210101_P01_WALL-PANEL-ASSY-SIDE-LOWER-LH_CAD (Autodesk Fusion 360 design; units mm, degrees)
part number: 2026-10-31-21-33-22-907
description: WALL - PANEL FRAME - SIDE LOWER - LH | Vách trái - khung dưới | P01
part number: 211101
description: WALL - SKIN - SIDE LOWER - LH | Vách trái - tấm ốp alu dưới | P01
part number: 211301
description: WALL - CAVITY FILL - SIDE LOWER - LH | Vách trái - bông PET dưới | P01
part number: 211501
description: HARDWARE - STOP WASHER - Ø10.5 X Ø20 X 1.5 - AL | Long đen chặn nhôm | P01
part number: 831002
description: HARDWARE - RIVET NUT - M6 - SHEREX CAH3-610-4.2 | Tán rút M6 | P01
part number: 838003
description: HARDWARE - LOCATING SPIGOT - M6 X Ø8 - STAINLESS | Chốt định vị Ø8 | P01
part number: 831001
Autodesk Fusion 360 part; units mm, degrees
(part 1 of 2)
ref_plane "WorkPlane1" through (0, 0, 112.26) normal (0, 0, 1) x (1, 0, 0) in component "211101 WALL - PANEL FRAME - SIDE LOWER - LH"
sketch "SKETCH - RAIL - BOTTOM TUBE" plane through (0, 0, 112.26) normal (0, 0, 1) x (1, 0, 0) in component "211101 WALL - PANEL FRAME - SIDE LOWER - LH"
  line L0 (-1244, -642.74) -> (-1204, -642.74)
  line L1 (-1204, -642.74) -> (-1204, 847)
  line L2 (-1204, 847) -> (-1244, 847)
  line L3 (-1244, 847) -> (-1244, -642.74)
  dimension "d1746" = 40
  dimension "d1747" = 1489.74
  dimension "d1748" = 1244
  dimension "d1749" = 642.74
  constraint horizontal L0
  constraint vertical L1
  constraint horizontal L2
  constraint vertical L3
  measures "d1746" horizontal distance of L0.start L0.end
  measures "d1747" vertical distance of L0.start L2.end
  measures "d1748" horizontal distance of origin L0.start
  measures "d1749" vertical distance of origin L0.start
extrude "EXTRUDE - RAIL - BOTTOM TUBE" add sketch "SKETCH - RAIL - BOTTOM TUBE" along normal blind 20 makes body 1 in component "211101 WALL - PANEL FRAME - SIDE LOWER - LH"
ref_plane "WorkPlane2" through (0, 0, 113.46) normal (0, 0, 1) x (1, 0, 0) in component "211101 WALL - PANEL FRAME - SIDE LOWER - LH"
sketch "SKETCH - RAIL - BOTTOM BORE" plane through (0, 0, 113.46) normal (0, 0, 1) x (1, 0, 0) in component "211101 WALL - PANEL FRAME - SIDE LOWER - LH"
  line L0 (-1242.8, -642.74) -> (-1205.2, -642.74)
  line L1 (-1205.2, -642.74) -> (-1205.2, 847)
  line L2 (-1205.2, 847) -> (-1242.8, 847)
  line L3 (-1242.8, 847) -> (-1242.8, -642.74)
  dimension "d1754" = 37.6
  dimension "d1755" = 1489.74
  dimension "d1756" = 1242.8
  dimension "d1757" = 642.74
  constraint horizontal L0
  constraint vertical L1
  constraint horizontal L2
  constraint vertical L3
  measures "d1754" horizontal distance of L0.start L0.end
  measures "d1755" vertical distance of L0.start L2.end
  measures "d1756" horizontal distance of origin L0.start
  measures "d1757" vertical distance of origin L0.start
extrude "CUT - RAIL - BOTTOM BORE" cut sketch "SKETCH - RAIL - BOTTOM BORE" along normal blind 17.6 bodies 1 in component "211101 WALL - PANEL FRAME - SIDE LOWER - LH"
ref_plane "WorkPlane3" through (0, 0, 1235) normal (0, 0, 1) x (1, 0, 0) in component "211101 WALL - PANEL FRAME - SIDE LOWER - LH"
sketch "SKETCH - RAIL - TOP TUBE" plane through (0, 0, 1235) normal (0, 0, 1) x (1, 0, 0) in component "211101 WALL - PANEL FRAME - SIDE LOWER - LH"
  line L0 (-1244, -642.74) -> (-1204, -642.74)
  line L1 (-1204, -642.74) -> (-1204, 847)
  line L2 (-1204, 847) -> (-1244, 847)
  line L3 (-1244, 847) -> (-1244, -642.74)
  dimension "d1762" = 40
  dimension "d1763" = 1489.74
  dimension "d1764" = 1244
  dimension "d1765" = 642.74
  constraint horizontal L0
  constraint vertical L1
  constraint horizontal L2
  constraint vertical L3
  measures "d1762" horizontal distance of L0.start L0.end
  measures "d1763" vertical distance of L0.start L2.end
  measures "d1764" horizontal distance of origin L0.start
  measures "d1765" vertical distance of origin L0.start
extrude "EXTRUDE - RAIL - TOP TUBE" add sketch "SKETCH - RAIL - TOP TUBE" along normal blind 20 separate body makes body 2 in component "211101 WALL - PANEL FRAME - SIDE LOWER - LH"
ref_plane "WorkPlane4" through (0, 0, 1236.2) normal (0, 0, 1) x (1, 0, 0) in component "211101 WALL - PANEL FRAME - SIDE LOWER - LH"
sketch "SKETCH - RAIL - TOP BORE" plane through (0, 0, 1236.2) normal (0, 0, 1) x (1, 0, 0) in component "211101 WALL - PANEL FRAME - SIDE LOWER - LH"
  line L0 (-1242.8, -642.74) -> (-1205.2, -642.74)
  line L1 (-1205.2, -642.74) -> (-1205.2, 847)
  line L2 (-1205.2, 847) -> (-1242.8, 847)
  line L3 (-1242.8, 847) -> (-1242.8, -642.74)
  dimension "d1770" = 37.6
  dimension "d1771" = 1489.74
  dimension "d1772" = 1242.8
  dimension "d1773" = 642.74
  constraint horizontal L0
  constraint vertical L1
  constraint horizontal L2
  constraint vertical L3
  measures "d1770" horizontal distance of L0.start L0.end
  measures "d1771" vertical distance of L0.start L2.end
  measures "d1772" horizontal distance of origin L0.start
  measures "d1773" vertical distance of origin L0.start
extrude "CUT - RAIL - TOP BORE" cut sketch "SKETCH - RAIL - TOP BORE" along normal blind 17.6 bodies 2 in component "211101 WALL - PANEL FRAME - SIDE LOWER - LH"
ref_plane "WorkPlane5" through (0, 0, 132.26) normal (0, 0, 1) x (1, 0, 0) in component "211101 WALL - PANEL FRAME - SIDE LOWER - LH"
sketch "SKETCH - STILE - FRONT TUBE" plane through (0, 0, 132.26) normal (0, 0, 1) x (1, 0, 0) in component "211101 WALL - PANEL FRAME - SIDE LOWER - LH"
  line L0 (-1244, -642.74) -> (-1204, -642.74)
  line L1 (-1204, -642.74) -> (-1204, -622.74)
  line L2 (-1204, -622.74) -> (-1244, -622.74)
  line L3 (-1244, -622.74) -> (-1244, -642.74)
  dimension "d1778" = 40
  dimension "d1779" = 20
  dimension "d1780" = 1244
  dimension "d1781" = 642.74
  constraint horizontal L0
  constraint vertical L1
  constraint horizontal L2
  constraint vertical L3
  measures "d1778" horizontal distance of L0.start L0.end
  measures "d1779" vertical distance of L0.start L2.end
  measures "d1780" horizontal distance of origin L0.start
  measures "d1781" vertical distance of origin L0.start
extrude "EXTRUDE - STILE - FRONT TUBE" add sketch "SKETCH - STILE - FRONT TUBE" along normal blind 1102.74 separate body makes body 3 in component "211101 WALL - PANEL FRAME - SIDE LOWER - LH"
ref_plane "WorkPlane6" through (0, 0, 132.26) normal (0, 0, 1) x (1, 0, 0) in component "211101 WALL - PANEL FRAME - SIDE LOWER - LH"
sketch "SKETCH - STILE - FRONT BORE" plane through (0, 0, 132.26) normal (0, 0, 1) x (1, 0, 0) in component "211101 WALL - PANEL FRAME - SIDE LOWER - LH"
  line L0 (-1242.8, -641.54) -> (-1205.2, -641.54)
  line L1 (-1205.2, -641.54) -> (-1205.2, -623.94)
  line L2 (-1205.2, -623.94) -> (-1242.8, -623.94)
  line L3 (-1242.8, -623.94) -> (-1242.8, -641.54)
  dimension "d1786" = 37.6
  dimension "d1787" = 17.6
  dimension "d1788" = 1242.8
  dimension "d1789" = 641.54
  constraint horizontal L0
  constraint vertical L1
  constraint horizontal L2
  constraint vertical L3
  measures "d1786" horizontal distance of L0.start L0.end
  measures "d1787" vertical distance of L0.start L2.end
  measures "d1788" horizontal distance of origin L0.start
  measures "d1789" vertical distance of origin L0.start
extrude "CUT - STILE - FRONT BORE" cut sketch "SKETCH - STILE - FRONT BORE" along normal blind 1102.74 bodies 3 in component "211101 WALL - PANEL FRAME - SIDE LOWER - LH"
ref_plane "WorkPlane7" through (0, 0, 132.26) normal (0, 0, 1) x (1, 0, 0) in component "211101 WALL - PANEL FRAME - SIDE LOWER - LH"
sketch "SKETCH - STILE - BACK TUBE" plane through (0, 0, 132.26) normal (0, 0, 1) x (1, 0, 0) in component "211101 WALL - PANEL FRAME - SIDE LOWER - LH"
  line L0 (-1244, 807) -> (-1204, 807)
  line L1 (-1204, 807) -> (-1204, 847)
  line L2 (-1204, 847) -> (-1244, 847)
  line L3 (-1244, 847) -> (-1244, 807)
  dimension "d1794" = 40
  dimension "d1795" = 40
  dimension "d1796" = 1244
  dimension "d1797" = 807
  constraint horizontal L0
  constraint vertical L1
  constraint horizontal L2
  constraint vertical L3
  measures "d1794" horizontal distance of L0.start L0.end
  measures "d1795" vertical distance of L0.start L2.end
  measures "d1796" horizontal distance of origin L0.start
  measures "d1797" vertical distance of origin L0.start
extrude "EXTRUDE - STILE - BACK TUBE" add sketch "SKETCH - STILE - BACK TUBE" along normal blind 1102.74 separate body makes body 4 in component "211101 WALL - PANEL FRAME - SIDE LOWER - LH"
ref_plane "WorkPlane8" through (0, 0, 132.26) normal (0, 0, 1) x (1, 0, 0) in component "211101 WALL - PANEL FRAME - SIDE LOWER - LH"
sketch "SKETCH - STILE - BACK BORE" plane through (0, 0, 132.26) normal (0, 0, 1) x (1, 0, 0) in component "211101 WALL - PANEL FRAME - SIDE LOWER - LH"
  line L0 (-1242.8, 808.2) -> (-1205.2, 808.2)
  line L1 (-1205.2, 808.2) -> (-1205.2, 845.8)
  line L2 (-1205.2, 845.8) -> (-1242.8, 845.8)
  line L3 (-1242.8, 845.8) -> (-1242.8, 808.2)
  dimension "d1802" = 37.6
  dimension "d1803" = 37.6
  dimension "d1804" = 1242.8
  dimension "d1805" = 808.2
  constraint horizontal L0
  constraint vertical L1
  constraint horizontal L2
  constraint vertical L3
  measures "d1802" horizontal distance of L0.start L0.end
  measures "d1803" vertical distance of L0.start L2.end
  measures "d1804" horizontal distance of origin L0.start
  measures "d1805" vertical distance of origin L0.start
extrude "CUT - STILE - BACK BORE" cut sketch "SKETCH - STILE - BACK BORE" along normal blind 1102.74 bodies 4 in component "211101 WALL - PANEL FRAME - SIDE LOWER - LH"
ref_plane "WorkPlane9" through (0, 0, 132.26) normal (0, 0, 1) x (1, 0, 0) in component "211101 WALL - PANEL FRAME - SIDE LOWER - LH"
sketch "SKETCH - STILE - MID 1 TUBE" plane through (0, 0, 132.26) normal (0, 0, 1) x (1, 0, 0) in component "211101 WALL - PANEL FRAME - SIDE LOWER - LH"
  line L0 (-1244, -277.805) -> (-1204, -277.805)
  line L1 (-1204, -277.805) -> (-1204, -257.805)
  line L2 (-1204, -257.805) -> (-1244, -257.805)
  line L3 (-1244, -257.805) -> (-1244, -277.805)
  dimension "d1810" = 40
  dimension "d1811" = 20
  dimension "d1812" = 1244
  dimension "d1813" = 277.805
  constraint horizontal L0
  constraint vertical L1
  constraint horizontal L2
  constraint vertical L3
  measures "d1810" horizontal distance of L0.start L0.end
  measures "d1811" vertical distance of L0.start L2.end
  measures "d1812" horizontal distance of origin L0.start
  measures "d1813" vertical distance of origin L0.start
extrude "EXTRUDE - STILE - MID 1 TUBE" add sketch "SKETCH - STILE - MID 1 TUBE" along normal blind 1102.74 separate body makes body 5 in component "211101 WALL - PANEL FRAME - SIDE LOWER - LH"
ref_plane "WorkPlane10" through (0, 0, 132.26) normal (0, 0, 1) x (1, 0, 0) in component "211101 WALL - PANEL FRAME - SIDE LOWER - LH"
sketch "SKETCH - STILE - MID 1 BORE" plane through (0, 0, 132.26) normal (0, 0, 1) x (1, 0, 0) in component "211101 WALL - PANEL FRAME - SIDE LOWER - LH"
  line L0 (-1243, -276.805) -> (-1205, -276.805)
  line L1 (-1205, -276.805) -> (-1205, -258.805)
  line L2 (-1205, -258.805) -> (-1243, -258.805)
  line L3 (-1243, -258.805) -> (-1243, -276.805)
  dimension "d1818" = 38
  dimension "d1819" = 18
  dimension "d1820" = 1243
  dimension "d1821" = 276.805
  constraint horizontal L0
  constraint vertical L1
  constraint horizontal L2
  constraint vertical L3
  measures "d1818" horizontal distance of L0.start L0.end
  measures "d1819" vertical distance of L0.start L2.end
  measures "d1820" horizontal distance of origin L0.start
  measures "d1821" vertical distance of origin L0.start
extrude "CUT - STILE - MID 1 BORE" cut sketch "SKETCH - STILE - MID 1 BORE" along normal blind 1102.74 bodies 5 in component "211101 WALL - PANEL FRAME - SIDE LOWER - LH"
pattern_linear "PATTERN - STILES - MID" count 3 spacing 364.935 along (0, 1, 0) of bodies 5 makes body 6 at (-1217.3333, 107.13, 499.84) makes body 7 at (-1217.3333, 472.065, 499.84) in component "211101 WALL - PANEL FRAME - SIDE LOWER - LH"
ref_plane "WorkPlane1" through (0, 0, 112.26) normal (0, 0, 1) x (1, 0, 0) in component "211301 WALL - SKIN - SIDE LOWER - LH"
sketch "SKETCH - SKIN PLATE" plane through (0, 0, 112.26) normal (0, 0, 1) x (1, 0, 0) in component "211301 WALL - SKIN - SIDE LOWER - LH"
  line L0 (-1250, -642.74) -> (-1247, -642.74)
  line L1 (-1247, -642.74) -> (-1247, 850)
  line L2 (-1247, 850) -> (-1250, 850)
  line L3 (-1250, 850) -> (-1250, -642.74)
  dimension "d1830" = 3
  dimension "d1831" = 1492.74
  dimension "d1832" = 1250
  dimension "d1833" = 642.74
  constraint horizontal L0
  constraint vertical L1
  constraint horizontal L2
  constraint vertical L3
  measures "d1830" horizontal distance of L0.start L0.end
  measures "d1831" vertical distance of L0.start L2.end
  measures "d1832" horizontal distance of origin L0.start
  measures "d1833" vertical distance of origin L0.start
extrude "EXTRUDE - SKIN PLATE" add sketch "SKETCH - SKIN PLATE" along normal blind 1142.74 separate body makes body 8 in component "211301 WALL - SKIN - SIDE LOWER - LH"
ref_plane "WorkPlane2" through (0, 0, 112.26) normal (0, 0, 1) x (1, 0, 0) in component "211301 WALL - SKIN - SIDE LOWER - LH"
sketch "SKETCH - SKIN BACK RETURN" plane through (0, 0, 112.26) normal (0, 0, 1) x (1, 0, 0) in component "211301 WALL - SKIN - SIDE LOWER - LH"
  line L0 (-1247, 847) -> (-1204, 847)
  line L1 (-1204, 847) -> (-1204, 850)
  line L2 (-1204, 850) -> (-1247, 850)
  line L3 (-1247, 850) -> (-1247, 847)
  dimension "d1838" = 43
  dimension "d1839" = 3
  dimension "d1840" = 1247
  dimension "d1841" = 847
  constraint horizontal L0
  constraint vertical L1
  constraint horizontal L2
  constraint vertical L3
  measures "d1838" horizontal distance of L0.start L0.end
  measures "d1839" vertical distance of L0.start L2.end
  measures "d1840" horizontal distance of origin L0.start
  measures "d1841" vertical distance of origin L0.start
extrude "JOIN - SKIN BACK RETURN" add sketch "SKETCH - SKIN BACK RETURN" along normal blind 1142.74 bodies 8 in component "211301 WALL - SKIN - SIDE LOWER - LH"
ref_plane "WorkPlane1" through (0, 0, 132.26) normal (0, 0, 1) x (1, 0, 0) in component "211501 WALL - CAVITY FILL - SIDE LOWER - LH"
sketch "SKETCH - FILL BAY 1" plane through (0, 0, 132.26) normal (0, 0, 1) x (1, 0, 0) in component "211501 WALL - CAVITY FILL - SIDE LOWER - LH"
  line L0 (-1244, -622.74) -> (-1204, -622.74)
  line L1 (-1204, -622.74) -> (-1204, -277.805)
  line L2 (-1204, -277.805) -> (-1244, -277.805)
  line L3 (-1244, -277.805) -> (-1244, -622.74)
  dimension "d1846" = 40
  dimension "d1847" = 344.935
  dimension "d1848" = 1244
  dimension "d1849" = 622.74
  constraint horizontal L0
  constraint vertical L1
  constraint horizontal L2
  constraint vertical L3
  measures "d1846" horizontal distance of L0.start L0.end
  measures "d1847" vertical distance of L0.start L2.end
  measures "d1848" horizontal distance of origin L0.start
  measures "d1849" vertical distance of origin L0.start
extrude "EXTRUDE - FILL BAY 1" add sketch "SKETCH - FILL BAY 1" along normal blind 1102.74 separate body makes body 9 in component "211501 WALL - CAVITY FILL - SIDE LOWER - LH"
pattern_linear "PATTERN - FILL BAYS" count 3 spacing 364.935 along (0, 1, 0) of bodies 9 makes body 10 at (-1244, -27.8483, 499.84) makes body 11 at (-1244, 337.0867, 499.84) in component "211501 WALL - CAVITY FILL - SIDE LOWER - LH"
ref_plane "WorkPlane2" through (0, 0, 132.26) normal (0, 0, 1) x (1, 0, 0) in component "211501 WALL - CAVITY FILL - SIDE LOWER - LH"
sketch "SKETCH - FILL BAY LAST" plane through (0, 0, 132.26) normal (0, 0, 1) x (1, 0, 0) in component "211501 WALL - CAVITY FILL - SIDE LOWER - LH"
  line L0 (-1244, 472.065) -> (-1204, 472.065)
  line L1 (-1204, 472.065) -> (-1204, 807)
  line L2 (-1204, 807) -> (-1244, 807)
  line L3 (-1244, 807) -> (-1244, 472.065)
  dimension "d1858" = 40
  dimension "d1859" = 334.935
  dimension "d1860" = 1244
  dimension "d1861" = 472.065
  constraint horizontal L0
  constraint vertical L1
  constraint horizontal L2
  constraint vertical L3
  measures "d1858" horizontal distance of L0.start L0.end
  measures "d1859" vertical distance of L0.start L2.end
  measures "d1860" horizontal distance of origin L0.start
  measures "d1861" vertical distance of origin L0.start
extrude "EXTRUDE - FILL BAY LAST" add sketch "SKETCH - FILL BAY LAST" along normal blind 1102.74 separate body makes body 12 in component "211501 WALL - CAVITY FILL - SIDE LOWER - LH"
ref_plane "WorkPlane3" through (0, 0, 132.26) normal (0, 0, 1) x (1, 0, 0) in component "211501 WALL - CAVITY FILL - SIDE LOWER - LH"
sketch "SKETCH - FILL POCKET BOTTOM BOLT 1" plane through (0, 0, 132.26) normal (0, 0, 1) x (1, 0, 0) in component "211501 WALL - CAVITY FILL - SIDE LOWER - LH"
  line L0 (-1244, -452.74) -> (-1204, -452.74)
  line L1 (-1204, -452.74) -> (-1204, -392.74)
  line L2 (-1204, -392.74) -> (-1244, -392.74)
  line L3 (-1244, -392.74) -> (-1244, -452.74)
  dimension "d1866" = 40
  dimension "d1867" = 60
  dimension "d1868" = 1244
  dimension "d1869" = 452.74
  constraint horizontal L0
  constraint vertical L1
  constraint horizontal L2
  constraint vertical L3
  measures "d1866" horizontal distance of L0.start L0.end
  measures "d1867" vertical distance of L0.start L2.end
  measures "d1868" horizontal distance of origin L0.start
  measures "d1869" vertical distance of origin L0.start
extrude "CUT - FILL POCKET BOTTOM BOLT 1" cut sketch "SKETCH - FILL POCKET BOTTOM BOLT 1" along normal blind 60 bodies 9 in component "211501 WALL - CAVITY FILL - SIDE LOWER - LH"
ref_plane "WorkPlane4" through (0, 0, 132.26) normal (0, 0, 1) x (1, 0, 0) in component "211501 WALL - CAVITY FILL - SIDE LOWER - LH"
sketch "SKETCH - FILL POCKET BOTTOM BOLT 2" plane through (0, 0, 132.26) normal (0, 0, 1) x (1, 0, 0) in component "211501 WALL - CAVITY FILL - SIDE LOWER - LH"
  line L0 (-1244, -101.8267) -> (-1204, -101.8267)
  line L1 (-1204, -101.8267) -> (-1204, -41.8267)
  line L2 (-1204, -41.8267) -> (-1244, -41.8267)
  line L3 (-1244, -41.8267) -> (-1244, -101.8267)
  dimension "d1874" = 40
  dimension "d1875" = 60
  dimension "d1876" = 1244
  dimension "d1877" = 101.8267
  constraint horizontal L0
  constraint vertical L1
  constraint horizontal L2
  constraint vertical L3
  measures "d1874" horizontal distance of L0.start L0.end
  measures "d1875" vertical distance of L0.start L2.end
  measures "d1876" horizontal distance of origin L0.start
  measures "d1877" vertical distance of origin L0.start
extrude "CUT - FILL POCKET BOTTOM BOLT 2" cut sketch "SKETCH - FILL POCKET BOTTOM BOLT 2" along normal blind 60 bodies 10 in component "211501 WALL - CAVITY FILL - SIDE LOWER - LH"
ref_plane "WorkPlane5" through (0, 0, 132.26) normal (0, 0, 1) x (1, 0, 0) in component "211501 WALL - CAVITY FILL - SIDE LOWER - LH"
sketch "SKETCH - FILL POCKET BOTTOM BOLT 3" plane through (0, 0, 132.26) normal (0, 0, 1) x (1, 0, 0) in component "211501 WALL - CAVITY FILL - SIDE LOWER - LH"
  line L0 (-1244, 249.0867) -> (-1204, 249.0867)
  line L1 (-1204, 249.0867) -> (-1204, 309.0867)
  line L2 (-1204, 309.0867) -> (-1244, 309.0867)
  line L3 (-1244, 309.0867) -> (-1244, 249.0867)
  dimension "d1882" = 40
  dimension "d1883" = 60
  dimension "d1884" = 1244
  dimension "d1885" = 249.0867
  constraint horizontal L0
  constraint vertical L1
  constraint horizontal L2
  constraint vertical L3
  measures "d1882" horizontal distance of L0.start L0.end
  measures "d1883" vertical distance of L0.start L2.end
  measures "d1884" horizontal distance of origin L0.start
  measures "d1885" vertical distance of origin L0.start
extrude "CUT - FILL POCKET BOTTOM BOLT 3" cut sketch "SKETCH - FILL POCKET BOTTOM BOLT 3" along normal blind 60 bodies 11 in component "211501 WALL - CAVITY FILL - SIDE LOWER - LH"
ref_plane "WorkPlane6" through (0, 0, 132.26) normal (0, 0, 1) x (1, 0, 0) in component "211501 WALL - CAVITY FILL - SIDE LOWER - LH"
sketch "SKETCH - FILL POCKET BOTTOM BOLT 4" plane through (0, 0, 132.26) normal (0, 0, 1) x (1, 0, 0) in component "211501 WALL - CAVITY FILL - SIDE LOWER - LH"
  line L0 (-1244, 600) -> (-1204, 600)
  line L1 (-1204, 600) -> (-1204, 660)
  line L2 (-1204, 660) -> (-1244, 660)
  line L3 (-1244, 660) -> (-1244, 600)
  dimension "d1890" = 40
  dimension "d1891" = 60
  dimension "d1892" = 1244
  dimension "d1893" = 600
  constraint horizontal L0
  constraint vertical L1
  constraint horizontal L2
  constraint vertical L3
  measures "d1890" horizontal distance of L0.start L0.end
  measures "d1891" vertical distance of L0.start L2.end
  measures "d1892" horizontal distance of origin L0.start
  measures "d1893" vertical distance of origin L0.start
extrude "CUT - FILL POCKET BOTTOM BOLT 4" cut sketch "SKETCH - FILL POCKET BOTTOM BOLT 4" along normal blind 60 bodies 12 in component "211501 WALL - CAVITY FILL - SIDE LOWER - LH"
ref_plane "WorkPlane7" through (0, 0, 302.26) normal (0, 0, 1) x (1, 0, 0) in component "211501 WALL - CAVITY FILL - SIDE LOWER - LH"
sketch "SKETCH - FILL POCKET DECOR BOLT 1" plane through (0, 0, 302.26) normal (0, 0, 1) x (1, 0, 0) in component "211501 WALL - CAVITY FILL - SIDE LOWER - LH"
  line L0 (-1244, -622.74) -> (-1204, -622.74)
  line L1 (-1204, -622.74) -> (-1204, -562.74)
  line L2 (-1204, -562.74) -> (-1244, -562.74)
  line L3 (-1244, -562.74) -> (-1244, -622.74)
  dimension "d1898" = 40
  dimension "d1899" = 60
  dimension "d1900" = 1244
  dimension "d1901" = 622.74
  constraint horizontal L0
  constraint vertical L1
  constraint horizontal L2
  constraint vertical L3
  measures "d1898" horizontal distance of L0.start L0.end
  measures "d1899" vertical distance of L0.start L2.end
  measures "d1900" horizontal distance of origin L0.start
  measures "d1901" vertical distance of origin L0.start
extrude "CUT - FILL POCKET DECOR BOLT 1" cut sketch "SKETCH - FILL POCKET DECOR BOLT 1" along normal blind 60 bodies 9 in component "211501 WALL - CAVITY FILL - SIDE LOWER - LH"
ref_plane "WorkPlane8" through (0, 0, 653.63) normal (0, 0, 1) x (1, 0, 0) in component "211501 WALL - CAVITY FILL - SIDE LOWER - LH"
sketch "SKETCH - FILL POCKET DECOR BOLT 2" plane through (0, 0, 653.63) normal (0, 0, 1) x (1, 0, 0) in component "211501 WALL - CAVITY FILL - SIDE LOWER - LH"
  line L0 (-1244, -622.74) -> (-1204, -622.74)
  line L1 (-1204, -622.74) -> (-1204, -562.74)
  line L2 (-1204, -562.74) -> (-1244, -562.74)
  line L3 (-1244, -562.74) -> (-1244, -622.74)
  dimension "d1906" = 40
  dimension "d1907" = 60
  dimension "d1908" = 1244
  dimension "d1909" = 622.74
  constraint horizontal L0
  constraint vertical L1
  constraint horizontal L2
  constraint vertical L3
  measures "d1906" horizontal distance of L0.start L0.end
  measures "d1907" vertical distance of L0.start L2.end
  measures "d1908" horizontal distance of origin L0.start
  measures "d1909" vertical distance of origin L0.start
extrude "CUT - FILL POCKET DECOR BOLT 2" cut sketch "SKETCH - FILL POCKET DECOR BOLT 2" along normal blind 60 bodies 9 in component "211501 WALL - CAVITY FILL - SIDE LOWER - LH"
ref_plane "WorkPlane9" through (0, 0, 1005) normal (0, 0, 1) x (1, 0, 0) in component "211501 WALL - CAVITY FILL - SIDE LOWER - LH"
sketch "SKETCH - FILL POCKET DECOR BOLT 3" plane through (0, 0, 1005) normal (0, 0, 1) x (1, 0, 0) in component "211501 WALL - CAVITY FILL - SIDE LOWER - LH"
  line L0 (-1244, -622.74) -> (-1204, -622.74)
  line L1 (-1204, -622.74) -> (-1204, -562.74)
  line L2 (-1204, -562.74) -> (-1244, -562.74)
  line L3 (-1244, -562.74) -> (-1244, -622.74)
  dimension "d1914" = 40
  dimension "d1915" = 60
  dimension "d1916" = 1244
  dimension "d1917" = 622.74
  constraint horizontal L0
  constraint vertical L1
  constraint horizontal L2
  constraint vertical L3
  measures "d1914" horizontal distance of L0.start L0.end
  measures "d1915" vertical distance of L0.start L2.end
  measures "d1916" horizontal distance of origin L0.start
  measures "d1917" vertical distance of origin L0.start
extrude "CUT - FILL POCKET DECOR BOLT 3" cut sketch "SKETCH - FILL POCKET DECOR BOLT 3" along normal blind 60 bodies 9 in component "211501 WALL - CAVITY FILL - SIDE LOWER - LH"
ref_plane "WorkPlane11" through (0, 0, 112.26) normal (0, 0, 1) x (1, 0, 0) in component "211101 WALL - PANEL FRAME - SIDE LOWER - LH"
sketch "HOLE CENTRE - BOTTOM RAIL BOLT CLEARANCE 1" plane through (0, 0, 112.26) normal (0, 0, 1) x (1, 0, 0) in component "211101 WALL - PANEL FRAME - SIDE LOWER - LH"
  point P0 (-1224, -422.74)
  dimension "d1922" = 1224
  dimension "d1923" = 422.74
  measures "d1922" horizontal distance of origin P0
  measures "d1923" vertical distance of origin P0
hole "HOLE - BOTTOM RAIL BOLT CLEARANCE 1" at (-1224, -422.74, 112.26) direction (0, 0, 1) diameter 7 depth 1.2 tip angle 118 bodies 1 in component "211101 WALL - PANEL FRAME - SIDE LOWER - LH"
ref_plane "WorkPlane12" through (0, 0, 132.26) normal (0, 0, 1) x (1, 0, 0) in component "211101 WALL - PANEL FRAME - SIDE LOWER - LH"
sketch "HOLE CENTRE - BOTTOM RAIL KEY ACCESS 1" plane through (0, 0, 132.26) normal (0, 0, 1) x (1, 0, 0) in component "211101 WALL - PANEL FRAME - SIDE LOWER - LH"
  point P0 (-1224, -422.74)
  dimension "d1929" = 1224
  dimension "d1930" = 422.74
  measures "d1929" horizontal distance of origin P0
  measures "d1930" vertical distance of origin P0
hole "HOLE - BOTTOM RAIL KEY ACCESS 1" at (-1224, -422.74, 132.26) direction (0, 0, -1) diameter 19 depth 1.2 tip angle 118 bodies 1 in component "211101 WALL - PANEL FRAME - SIDE LOWER - LH"
pattern_linear "PATTERN - BOTTOM RAIL BOLT HOLES" count 4 spacing 350.9133 along (0, 1, 0) of "HOLE - BOTTOM RAIL BOLT CLEARANCE 1", "HOLE - BOTTOM RAIL KEY ACCESS 1" in component "211101 WALL - PANEL FRAME - SIDE LOWER - LH"
ref_plane "WorkPlane13" through (0, 0, 112.26) normal (0, 0, 1) x (1, 0, 0) in component "211101 WALL - PANEL FRAME - SIDE LOWER - LH"
sketch "HOLE CENTRE - BOTTOM RAIL SPIGOT ROUND" plane through (0, 0, 112.26) normal (0, 0, 1) x (1, 0, 0) in component "211101 WALL - PANEL FRAME - SIDE LOWER - LH"
  point P0 (-1224, -542.74)
  dimension "d1940" = 1224
  dimension "d1941" = 542.74
  measures "d1940" horizontal distance of origin P0
  measures "d1941" vertical distance of origin P0
hole "HOLE - BOTTOM RAIL SPIGOT ROUND" at (-1224, -542.74, 112.26) direction (0, 0, 1) diameter 8.5 depth 1.2 tip angle 118 bodies 1 in component "211101 WALL - PANEL FRAME - SIDE LOWER - LH"
ref_plane "WorkPlane14" through (0, 0, 112.26) normal (0, 0, 1) x (1, 0, 0) in component "211101 WALL - PANEL FRAME - SIDE LOWER - LH"
sketch "SKETCH - BOTTOM RAIL SPIGOT SLOT" plane through (0, 0, 112.26) normal (0, 0, 1) x (1, 0, 0) in component "211101 WALL - PANEL FRAME - SIDE LOWER - LH"
  line L0 (-1226.75, 745.75) -> (-1221.25, 745.75)
  line L1 (-1221.25, 745.75) -> (-1221.25, 754.25)
  line L2 (-1221.25, 754.25) -> (-1226.75, 754.25)
  line L3 (-1226.75, 754.25) -> (-1226.75, 745.75)
  dimension "d1947" = 5.5
  dimension "d1948" = 8.5
  dimension "d1949" = 1226.75
  dimension "d1950" = 745.75
  constraint horizontal L0
  constraint vertical L1
  constraint horizontal L2
  constraint vertical L3
  measures "d1947" horizontal distance of L0.start L0.end
  measures "d1948" vertical distance of L0.start L2.end
  measures "d1949" horizontal distance of origin L0.start
  measures "d1950" vertical distance of origin L0.start
extrude "CUT - BOTTOM RAIL SPIGOT SLOT" cut sketch "SKETCH - BOTTOM RAIL SPIGOT SLOT" along normal blind 1.2 bodies 1 in component "211101 WALL - PANEL FRAME - SIDE LOWER - LH"
ref_plane "WorkPlane15" through (0, 0, 112.26) normal (0, 0, 1) x (1, 0, 0) in component "211101 WALL - PANEL FRAME - SIDE LOWER - LH"
sketch "HOLE CENTRE - BOTTOM RAIL SPIGOT SLOT END 1" plane through (0, 0, 112.26) normal (0, 0, 1) x (1, 0, 0) in component "211101 WALL - PANEL FRAME - SIDE LOWER - LH"
  point P0 (-1226.75, 750)
  dimension "d1955" = 1226.75
  dimension "d1956" = 750
  measures "d1955" horizontal distance of origin P0
  measures "d1956" vertical distance of origin P0
hole "HOLE - BOTTOM RAIL SPIGOT SLOT END 1" at (-1226.75, 750, 112.26) direction (0, 0, 1) diameter 8.5 depth 1.2 tip angle 118 bodies 1 in component "211101 WALL - PANEL FRAME - SIDE LOWER - LH"
ref_plane "WorkPlane16" through (0, 0, 112.26) normal (0, 0, 1) x (1, 0, 0) in component "211101 WALL - PANEL FRAME - SIDE LOWER - LH"
sketch "HOLE CENTRE - BOTTOM RAIL SPIGOT SLOT END 2" plane through (0, 0, 112.26) normal (0, 0, 1) x (1, 0, 0) in component "211101 WALL - PANEL FRAME - SIDE LOWER - LH"
  point P0 (-1221.25, 750)
  dimension "d1962" = 1221.25
  dimension "d1963" = 750
  measures "d1962" horizontal distance of origin P0
  measures "d1963" vertical distance of origin P0
hole "HOLE - BOTTOM RAIL SPIGOT SLOT END 2" at (-1221.25, 750, 112.26) direction (0, 0, 1) diameter 8.5 depth 1.2 tip angle 118 bodies 1 in component "211101 WALL - PANEL FRAME - SIDE LOWER - LH"
ref_plane "WorkPlane17" through (0, 0, 1255) normal (0, 0, 1) x (1, 0, 0) in component "211101 WALL - PANEL FRAME - SIDE LOWER - LH"
sketch "HOLE CENTRE - TOP RAIL RIVNUT 1" plane through (0, 0, 1255) normal (0, 0, 1) x (1, 0, 0) in component "211101 WALL - PANEL FRAME - SIDE LOWER - LH"
  point P0 (-1224, -422.74)
  dimension "d1969" = 1224
  dimension "d1970" = 422.74
  measures "d1969" horizontal distance of origin P0
  measures "d1970" vertical distance of origin P0
hole "HOLE - TOP RAIL RIVNUT 1" at (-1224, -422.74, 1255) direction (0, 0, -1) diameter 9.53 depth 1.2 tip angle 118 bodies 2 in component "211101 WALL - PANEL FRAME - SIDE LOWER - LH"
pattern_linear "PATTERN - TOP RAIL RIVNUTS" count 4 spacing 350.9133 along (0, 1, 0) of "HOLE - TOP RAIL RIVNUT 1" in component "211101 WALL - PANEL FRAME - SIDE LOWER - LH"
ref_plane "WorkPlane18" through (0, 0, 1255) normal (0, 0, 1) x (1, 0, 0) in component "211101 WALL - PANEL FRAME - SIDE LOWER - LH"
sketch "HOLE CENTRE - TOP RAIL SPIGOT RIVNUT FRONT" plane through (0, 0, 1255) normal (0, 0, 1) x (1, 0, 0) in component "211101 WALL - PANEL FRAME - SIDE LOWER - LH"
  point P0 (-1224, -542.74)
  dimension "d1980" = 1224
  dimension "d1981" = 542.74
  measures "d1980" horizontal distance of origin P0
  measures "d1981" vertical distance of origin P0
hole "HOLE - TOP RAIL SPIGOT RIVNUT FRONT" at (-1224, -542.74, 1255) direction (0, 0, -1) diameter 9.53 depth 1.2 tip angle 118 bodies 2 in component "211101 WALL - PANEL FRAME - SIDE LOWER - LH"
ref_plane "WorkPlane19" through (0, 0, 1255) normal (0, 0, 1) x (1, 0, 0) in component "211101 WALL - PANEL FRAME - SIDE LOWER - LH"
sketch "HOLE CENTRE - TOP RAIL SPIGOT RIVNUT BACK" plane through (0, 0, 1255) normal (0, 0, 1) x (1, 0, 0) in component "211101 WALL - PANEL FRAME - SIDE LOWER - LH"
  point P0 (-1224, 750)
  dimension "d1987" = 1224
  dimension "d1988" = 750
  measures "d1987" horizontal distance of origin P0
  measures "d1988" vertical distance of origin P0
hole "HOLE - TOP RAIL SPIGOT RIVNUT BACK" at (-1224, 750, 1255) direction (0, 0, -1) diameter 9.53 depth 1.2 tip angle 118 bodies 2 in component "211101 WALL - PANEL FRAME - SIDE LOWER - LH"
ref_plane "WorkPlane20" through (0, -642.74, 0) normal (0, 1, 0) x (0, 0, 1) in component "211101 WALL - PANEL FRAME - SIDE LOWER - LH"
sketch "HOLE CENTRE - FRONT STILE BOLT CLEARANCE 1" plane through (0, -642.74, 0) normal (0, 1, 0) x (1, 0, 0) in component "211101 WALL - PANEL FRAME - SIDE LOWER - LH"
  point P0 (-1224, -332.26)
  dimension "d1994" = 1224
  dimension "d1995" = 332.26
  measures "d1994" horizontal distance of origin P0
  measures "d1995" vertical distance of origin P0
hole "HOLE - FRONT STILE BOLT CLEARANCE 1" at (-1224, -642.74, 332.26) direction (0, 1, 0) diameter 7 depth 1.2 tip angle 118 bodies 3 in component "211101 WALL - PANEL FRAME - SIDE LOWER - LH"
ref_plane "WorkPlane21" through (0, -622.74, 0) normal (0, 1, 0) x (0, 0, 1) in component "211101 WALL - PANEL FRAME - SIDE LOWER - LH"
sketch "HOLE CENTRE - FRONT STILE KEY ACCESS 1" plane through (0, -622.74, 0) normal (0, 1, 0) x (1, 0, 0) in component "211101 WALL - PANEL FRAME - SIDE LOWER - LH"
  point P0 (-1224, -332.26)
  dimension "d2001" = 1224
  dimension "d2002" = 332.26
  measures "d2001" horizontal distance of origin P0
  measures "d2002" vertical distance of origin P0
hole "HOLE - FRONT STILE KEY ACCESS 1" at (-1224, -622.74, 332.26) direction (0, -1, 0) diameter 19 depth 1.2 tip angle 118 bodies 3 in component "211101 WALL - PANEL FRAME - SIDE LOWER - LH"
pattern_linear "PATTERN - FRONT STILE BOLT HOLES" count 3 spacing 351.37 along (0, 0, 1) of "HOLE - FRONT STILE BOLT CLEARANCE 1", "HOLE - FRONT STILE KEY ACCESS 1" in component "211101 WALL - PANEL FRAME - SIDE LOWER - LH"
ref_plane "WorkPlane22" through (-1204, 0, 0) normal (1, 0, 0) x (0, 1, 0) in component "211101 WALL - PANEL FRAME - SIDE LOWER - LH"
sketch "HOLE CENTRE - BACK STILE CORNER RIVNUT 1" plane through (-1204, 0, 0) normal (1, 0, 0) x (0, 0, -1) in component "211101 WALL - PANEL FRAME - SIDE LOWER - LH"
  point P0 (-332.26, 824)
  dimension "d2012" = 824
  dimension "d2013" = 332.26
  measures "d2012" vertical distance of origin P0
  measures "d2013" horizontal distance of origin P0
hole "HOLE - BACK STILE CORNER RIVNUT 1" at (-1204, 824, 332.26) direction (-1, 0, 0) diameter 9.53 depth 1.2 tip angle 118 bodies 4 in component "211101 WALL - PANEL FRAME - SIDE LOWER - LH"
pattern_linear "PATTERN - BACK STILE CORNER RIVNUTS" count 3 spacing 339.305 along (0, 0, 1) of "HOLE - BACK STILE CORNER RIVNUT 1" in component "211101 WALL - PANEL FRAME - SIDE LOWER - LH"
ref_plane "WorkPlane1" through (0, 0, 1255) normal (0, 0, 1) x (1, 0, 0) in component "831002 HARDWARE - STOP WASHER - Ø10.5 X Ø20 X 1.5 - AL"
sketch "SKETCH - STOP WASHER TOP RAIL" plane through (0, 0, 1255) normal (0, 0, 1) x (1, 0, 0) in component "831002 HARDWARE - STOP WASHER - Ø10.5 X Ø20 X 1.5 - AL"
  circle A0 centre (-1224, -422.74) radius 10
  circle A1 centre (-1224, -422.74) radius 5.25
  dimension "d2023" = 1224
  dimension "d2024" = 422.74
  dimension "d2025" = 20
  dimension "d2026" = 10.5
  measures "d2023" horizontal distance of origin A0.centre
  measures "d2024" vertical distance of origin A0.centre
  measures "d2025" diameter of A0
  measures "d2026" diameter of A1
extrude "EXTRUDE - STOP WASHER TOP RAIL" add sketch "SKETCH - STOP WASHER TOP RAIL" along normal blind 1.5 separate body makes body 13 in component "831002 HARDWARE - STOP WASHER - Ø10.5 X Ø20 X 1.5 - AL"
ref_plane "WorkPlane1" through (0, 0, 1256.5) normal (0, 0, 1) x (1, 0, 0) in component "838003 HARDWARE - RIVET NUT - M6 - SHEREX CAH3-610-4.2"
sketch "SKETCH - RIVNUT HEAD TOP RAIL" plane through (0, 0, 1256.5) normal (0, 0, 1) x (1, 0, 0) in component "838003 HARDWARE - RIVET NUT - M6 - SHEREX CAH3-610-4.2"
  circle A0 centre (-1224, -422.74) radius 6.48
  circle A1 centre (-1224, -422.74) radius 3
  dimension "d2031" = 1224
  dimension "d2032" = 422.74
  dimension "d2033" = 12.96
  dimension "d2034" = 6
  measures "d2031" horizontal distance of origin A0.centre
  measures "d2032" vertical distance of origin A0.centre
  measures "d2033" diameter of A0
  measures "d2034" diameter of A1
extrude "EXTRUDE - RIVNUT HEAD TOP RAIL" add sketch "SKETCH - RIVNUT HEAD TOP RAIL" along normal blind 0.76 separate body makes body 14 in component "838003 HARDWARE - RIVET NUT - M6 - SHEREX CAH3-610-4.2"
ref_plane "WorkPlane2" through (0, 0, 1256.5) normal (0, 0, 1) x (1, 0, 0) in component "838003 HARDWARE - RIVET NUT - M6 - SHEREX CAH3-610-4.2"
sketch "SKETCH - RIVNUT BODY TOP RAIL" plane through (0, 0, 1256.5) normal (0, 0, 1) x (1, 0, 0) in component "838003 HARDWARE - RIVET NUT - M6 - SHEREX CAH3-610-4.2"
  circle A0 centre (-1224, -422.74) radius 4.75
  circle A1 centre (-1224, -422.74) radius 3
  dimension "d2039" = 1224
  dimension "d2040" = 422.74
  dimension "d2041" = 9.5
  dimension "d2042" = 6
  measures "d2039" horizontal distance of origin A0.centre
  measures "d2040" vertical distance of origin A0.centre
  measures "d2041" diameter of A0
  measures "d2042" diameter of A1
extrude "EXTRUDE - RIVNUT BODY TOP RAIL" add sketch "SKETCH - RIVNUT BODY TOP RAIL" against normal blind 10.16 separate body makes body 15 in component "838003 HARDWARE - RIVET NUT - M6 - SHEREX CAH3-610-4.2"
combine "COMBINE - RIVNUT TOP RAIL" operation add target body 14 tool bodies 15 in component "838003 HARDWARE - RIVET NUT - M6 - SHEREX CAH3-610-4.2"
pattern_linear "PATTERN - STOP WASHER - TOP RAIL" count 4 spacing 350.9133 along (0, 1, 0) of bodies 13 makes body 16 at (-1225.3802, -80.1066, 1255) makes body 17 at (-1225.3802, 270.8068, 1255) makes body 18 at (-1222.6198, 638.2799, 1255) in component "831002 HARDWARE - STOP WASHER - Ø10.5 X Ø20 X 1.5 - AL"
pattern_linear "PATTERN - RIVNUT - TOP RAIL" count 4 spacing 350.9133 along (0, 1, 0) of bodies 14 makes body 19 at (-1221.833, -67.5998, 1249.7267) makes body 20 at (-1221.833, 283.3136, 1249.7267) makes body 21 at (-1221.833, 634.2269, 1249.7267) in component "838003 HARDWARE - RIVET NUT - M6 - SHEREX CAH3-610-4.2"
ref_plane "WorkPlane3" through (0, 0, 1255) normal (0, 0, 1) x (1, 0, 0) in component "838003 HARDWARE - RIVET NUT - M6 - SHEREX CAH3-610-4.2"
sketch "SKETCH - RIVNUT HEAD TOP RAIL SPIGOT FRONT" plane through (0, 0, 1255) normal (0, 0, 1) x (1, 0, 0) in component "838003 HARDWARE - RIVET NUT - M6 - SHEREX CAH3-610-4.2"
  circle A0 centre (-1224, -542.74) radius 6.48
  circle A1 centre (-1224, -542.74) radius 3
  dimension "d2057" = 1224
  dimension "d2058" = 542.74
  dimension "d2059" = 12.96
  dimension "d2060" = 6
  measures "d2057" horizontal distance of origin A0.centre
  measures "d2058" vertical distance of origin A0.centre
  measures "d2059" diameter of A0
  measures "d2060" diameter of A1
extrude "EXTRUDE - RIVNUT HEAD TOP RAIL SPIGOT FRONT" add sketch "SKETCH - RIVNUT HEAD TOP RAIL SPIGOT FRONT" along normal blind 0.76 separate body makes body 22 in component "838003 HARDWARE - RIVET NUT - M6 - SHEREX CAH3-610-4.2"
ref_plane "WorkPlane4" through (0, 0, 1255) normal (0, 0, 1) x (1, 0, 0) in component "838003 HARDWARE - RIVET NUT - M6 - SHEREX CAH3-610-4.2"
sketch "SKETCH - RIVNUT BODY TOP RAIL SPIGOT FRONT" plane through (0, 0, 1255) normal (0, 0, 1) x (1, 0, 0) in component "838003 HARDWARE - RIVET NUT - M6 - SHEREX CAH3-610-4.2"
  circle A0 centre (-1224, -542.74) radius 4.75
  circle A1 centre (-1224, -542.74) radius 3
  dimension "d2065" = 1224
  dimension "d2066" = 542.74
  dimension "d2067" = 9.5
  dimension "d2068" = 6
  measures "d2065" horizontal distance of origin A0.centre
  measures "d2066" vertical distance of origin A0.centre
  measures "d2067" diameter of A0
  measures "d2068" diameter of A1
extrude "EXTRUDE - RIVNUT BODY TOP RAIL SPIGOT FRONT" add sketch "SKETCH - RIVNUT BODY TOP RAIL SPIGOT FRONT" against normal blind 10.16 separate body makes body 23 in component "838003 HARDWARE - RIVET NUT - M6 - SHEREX CAH3-610-4.2"
combine "COMBINE - RIVNUT TOP RAIL SPIGOT FRONT" operation add target body 22 tool bodies 23 in component "838003 HARDWARE - RIVET NUT - M6 - SHEREX CAH3-610-4.2"
ref_plane "WorkPlane1" through (0, 0, 1255.76) normal (0, 0, 1) x (1, 0, 0) in component "831001 HARDWARE - LOCATING SPIGOT - M6 X Ø8 - STAINLESS"
sketch "SKETCH - SPIGOT PIN TOP RAIL SPIGOT FRONT" plane through (0, 0, 1255.76) normal (0, 0, 1) x (1, 0, 0) in component "831001 HARDWARE - LOCATING SPIGOT - M6 X Ø8 - STAINLESS"
  circle A0 centre (-1224, -542.74) radius 4
  dimension "d2075" = 1224
  dimension "d2076" = 542.74
  dimension "d2077" = 8
  measures "d2075" horizontal distance of origin A0.centre
  measures "d2076" vertical distance of origin A0.centre
  measures "d2077" diameter of A0
extrude "EXTRUDE - SPIGOT PIN TOP RAIL SPIGOT FRONT" add sketch "SKETCH - SPIGOT PIN TOP RAIL SPIGOT FRONT" along normal blind 7.24 separate body makes body 24 in component "831001 HARDWARE - LOCATING SPIGOT - M6 X Ø8 - STAINLESS"
ref_plane "WorkPlane2" through (0, 0, 1255.76) normal (0, 0, 1) x (1, 0, 0) in component "831001 HARDWARE - LOCATING SPIGOT - M6 X Ø8 - STAINLESS"
sketch "SKETCH - SPIGOT THREAD TOP RAIL SPIGOT FRONT" plane through (0, 0, 1255.76) normal (0, 0, 1) x (1, 0, 0) in component "831001 HARDWARE - LOCATING SPIGOT - M6 X Ø8 - STAINLESS"
  circle A0 centre (-1224, -542.74) radius 3
  dimension "d2082" = 1224
  dimension "d2083" = 542.74
  dimension "d2084" = 6
  measures "d2082" horizontal distance of origin A0.centre
  measures "d2083" vertical distance of origin A0.centre
  measures "d2084" diameter of A0
extrude "EXTRUDE - SPIGOT THREAD TOP RAIL SPIGOT FRONT" add sketch "SKETCH - SPIGOT THREAD TOP RAIL SPIGOT FRONT" against normal blind 10 separate body makes body 25 in component "831001 HARDWARE - LOCATING SPIGOT - M6 X Ø8 - STAINLESS"
combine "COMBINE - SPIGOT TOP RAIL SPIGOT FRONT" operation add target body 24 tool bodies 25 in component "831001 HARDWARE - LOCATING SPIGOT - M6 X Ø8 - STAINLESS"
ref_plane "WorkPlane5" through (0, 0, 1255) normal (0, 0, 1) x (1, 0, 0) in component "838003 HARDWARE - RIVET NUT - M6 - SHEREX CAH3-610-4.2"
sketch "SKETCH - RIVNUT HEAD TOP RAIL SPIGOT BACK" plane through (0, 0, 1255) normal (0, 0, 1) x (1, 0, 0) in component "838003 HARDWARE - RIVET NUT - M6 - SHEREX CAH3-610-4.2"
  circle A0 centre (-1224, 750) radius 6.48
  circle A1 centre (-1224, 750) radius 3
  dimension "d2091" = 1224
  dimension "d2092" = 750
  dimension "d2093" = 12.96
  dimension "d2094" = 6
  measures "d2091" horizontal distance of origin A0.centre
  measures "d2092" vertical distance of origin A0.centre
  measures "d2093" diameter of A0
  measures "d2094" diameter of A1
extrude "EXTRUDE - RIVNUT HEAD TOP RAIL SPIGOT BACK" add sketch "SKETCH - RIVNUT HEAD TOP RAIL SPIGOT BACK" along normal blind 0.76 separate body makes body 26 in component "838003 HARDWARE - RIVET NUT - M6 - SHEREX CAH3-610-4.2"
ref_plane "WorkPlane6" through (0, 0, 1255) normal (0, 0, 1) x (1, 0, 0) in component "838003 HARDWARE - RIVET NUT - M6 - SHEREX CAH3-610-4.2"
sketch "SKETCH - RIVNUT BODY TOP RAIL SPIGOT BACK" plane through (0, 0, 1255) normal (0, 0, 1) x (1, 0, 0) in component "838003 HARDWARE - RIVET NUT - M6 - SHEREX CAH3-610-4.2"
  circle A0 centre (-1224, 750) radius 4.75
  circle A1 centre (-1224, 750) radius 3
  dimension "d2099" = 1224
  dimension "d2100" = 750
  dimension "d2101" = 9.5
  dimension "d2102" = 6
  measures "d2099" horizontal distance of origin A0.centre
  measures "d2100" vertical distance of origin A0.centre
  measures "d2101" diameter of A0
  measures "d2102" diameter of A1
extrude "EXTRUDE - RIVNUT BODY TOP RAIL SPIGOT BACK" add sketch "SKETCH - RIVNUT BODY TOP RAIL SPIGOT BACK" against normal blind 10.16 separate body makes body 27 in component "838003 HARDWARE - RIVET NUT - M6 - SHEREX CAH3-610-4.2"
combine "COMBINE - RIVNUT TOP RAIL SPIGOT BACK" operation add target body 26 tool bodies 27 in component "838003 HARDWARE - RIVET NUT - M6 - SHEREX CAH3-610-4.2"
ref_plane "WorkPlane3" through (0, 0, 1255.76) normal (0, 0, 1) x (1, 0, 0) in component "831001 HARDWARE - LOCATING SPIGOT - M6 X Ø8 - STAINLESS"
sketch "SKETCH - SPIGOT PIN TOP RAIL SPIGOT BACK" plane through (0, 0, 1255.76) normal (0, 0, 1) x (1, 0, 0) in component "831001 HARDWARE - LOCATING SPIGOT - M6 X Ø8 - STAINLESS"
  circle A0 centre (-1224, 750) radius 4
  dimension "d2109" = 1224
  dimension "d2110" = 750
  dimension "d2111" = 8
  measures "d2109" horizontal distance of origin A0.centre
  measures "d2110" vertical distance of origin A0.centre
  measures "d2111" diameter of A0
extrude "EXTRUDE - SPIGOT PIN TOP RAIL SPIGOT BACK" add sketch "SKETCH - SPIGOT PIN TOP RAIL SPIGOT BACK" along normal blind 7.24 separate body makes body 28 in component "831001 HARDWARE - LOCATING SPIGOT - M6 X Ø8 - STAINLESS"
ref_plane "WorkPlane4" through (0, 0, 1255.76) normal (0, 0, 1) x (1, 0, 0) in component "831001 HARDWARE - LOCATING SPIGOT - M6 X Ø8 - STAINLESS"
sketch "SKETCH - SPIGOT THREAD TOP RAIL SPIGOT BACK" plane through (0, 0, 1255.76) normal (0, 0, 1) x (1, 0, 0) in component "831001 HARDWARE - LOCATING SPIGOT - M6 X Ø8 - STAINLESS"
  circle A0 centre (-1224, 750) radius 3
  dimension "d2116" = 1224
  dimension "d2117" = 750
  dimension "d2118" = 6
  measures "d2116" horizontal distance of origin A0.centre
  measures "d2117" vertical distance of origin A0.centre
  measures "d2118" diameter of A0
extrude "EXTRUDE - SPIGOT THREAD TOP RAIL SPIGOT BACK" add sketch "SKETCH - SPIGOT THREAD TOP RAIL SPIGOT BACK" against normal blind 10 separate body makes body 29 in component "831001 HARDWARE - LOCATING SPIGOT - M6 X Ø8 - STAINLESS"
combine "COMBINE - SPIGOT TOP RAIL SPIGOT BACK" operation add target body 28 tool bodies 29 in component "831001 HARDWARE - LOCATING SPIGOT - M6 X Ø8 - STAINLESS"
ref_plane "WorkPlane2" through (-1204, 0, 0) normal (1, 0, 0) x (0, 1, 0) in component "831002 HARDWARE - STOP WASHER - Ø10.5 X Ø20 X 1.5 - AL"
sketch "SKETCH - STOP WASHER BACK STILE CORNER" plane through (-1204, 0, 0) normal (1, 0, 0) x (0, 0, -1) in component "831002 HARDWARE - STOP WASHER - Ø10.5 X Ø20 X 1.5 - AL"
  circle A0 centre (-332.26, 824) radius 10
  circle A1 centre (-332.26, 824) radius 5.25
  dimension "d2125" = 824
  dimension "d2126" = 332.26
  dimension "d2127" = 20
  dimension "d2128" = 10.5
  measures "d2125" vertical distance of origin A0.centre
  measures "d2126" horizontal distance of origin A0.centre
  measures "d2127" diameter of A0
  measures "d2128" diameter of A1
extrude "EXTRUDE - STOP WASHER BACK STILE CORNER" add sketch "SKETCH - STOP WASHER BACK STILE CORNER" along normal blind 1.5 separate body makes body 30 in component "831002 HARDWARE - STOP WASHER - Ø10.5 X Ø20 X 1.5 - AL"
ref_plane "WorkPlane7" through (-1202.5, 0, 0) normal (1, 0, 0) x (0, 1, 0) in component "838003 HARDWARE - RIVET NUT - M6 - SHEREX CAH3-610-4.2"
sketch "SKETCH - RIVNUT HEAD BACK STILE CORNER" plane through (-1202.5, 0, 0) normal (1, 0, 0) x (0, 0, -1) in component "838003 HARDWARE - RIVET NUT - M6 - SHEREX CAH3-610-4.2"
  circle A0 centre (-332.26, 824) radius 6.48
  circle A1 centre (-332.26, 824) radius 3
  dimension "d2133" = 824
  dimension "d2134" = 332.26
  dimension "d2135" = 12.96
  dimension "d2136" = 6
  measures "d2133" vertical distance of origin A0.centre
  measures "d2134" horizontal distance of origin A0.centre
  measures "d2135" diameter of A0
  measures "d2136" diameter of A1
extrude "EXTRUDE - RIVNUT HEAD BACK STILE CORNER" add sketch "SKETCH - RIVNUT HEAD BACK STILE CORNER" along normal blind 0.76 separate body makes body 31 in component "838003 HARDWARE - RIVET NUT - M6 - SHEREX CAH3-610-4.2"
ref_plane "WorkPlane8" through (-1202.5, 0, 0) normal (1, 0, 0) x (0, 1, 0) in component "838003 HARDWARE - RIVET NUT - M6 - SHEREX CAH3-610-4.2"
sketch "SKETCH - RIVNUT BODY BACK STILE CORNER" plane through (-1202.5, 0, 0) normal (1, 0, 0) x (0, 0, -1) in component "838003 HARDWARE - RIVET NUT - M6 - SHEREX CAH3-610-4.2"
  circle A0 centre (-332.26, 824) radius 4.75
  circle A1 centre (-332.26, 824) radius 3
  dimension "d2141" = 824
  dimension "d2142" = 332.26
  dimension "d2143" = 9.5
  dimension "d2144" = 6
  measures "d2141" vertical distance of origin A0.centre
  measures "d2142" horizontal distance of origin A0.centre
  measures "d2143" diameter of A0
  measures "d2144" diameter of A1
extrude "EXTRUDE - RIVNUT BODY BACK STILE CORNER" add sketch "SKETCH - RIVNUT BODY BACK STILE CORNER" against normal blind 10.16 separate body makes body 32 in component "838003 HARDWARE - RIVET NUT - M6 - SHEREX CAH3-610-4.2"
combine "COMBINE - RIVNUT BACK STILE CORNER" operation add target body 31 tool bodies 32 in component "838003 HARDWARE - RIVET NUT - M6 - SHEREX CAH3-610-4.2"
pattern_linear "PATTERN - STOP WASHER - BACK STILE CORNER" count 3 spacing 339.305 along (0, 0, 1) of bodies 30 makes body 33 at (-1204, 815.9412, 673.914) makes body 34 at (-1204, 815.9412, 1013.219) in component "831002 HARDWARE - STOP WASHER - Ø10.5 X Ø20 X 1.5 - AL"
pattern_linear "PATTERN - RIVNUT - BACK STILE CORNER" count 3 spacing 339.305 along (0, 0, 1) of bodies 31 makes body 35 at (-1209.2733, 828.6778, 670.7402) makes body 36 at (-1209.2733, 828.6778, 1010.0452) in component "838003 HARDWARE - RIVET NUT - M6 - SHEREX CAH3-610-4.2"
component "211101 WALL - PANEL FRAME - SIDE LOWER - LH" placed x (1, 0, 0) y (0, 1, 0) z (0, 0, 1) at (0, 0, 0)
component "211301 WALL - SKIN - SIDE LOWER - LH" placed x (1, 0, 0) y (0, 1, 0) z (0, 0, 1) at (0, 0, 0)
component "211501 WALL - CAVITY FILL - SIDE LOWER - LH" placed x (1, 0, 0) y (0, 1, 0) z (0, 0, 1) at (0, 0, 0)
component "831002 HARDWARE - STOP WASHER - Ø10.5 X Ø20 X 1.5 - AL" placed x (1, 0, 0) y (0, 1, 0) z (0, 0, 1) at (0, 0, 0)
component "838003 HARDWARE - RIVET NUT - M6 - SHEREX CAH3-610-4.2" placed x (1, 0, 0) y (0, 1, 0) z (0, 0, 1) at (0, 0, 0)
component "831001 HARDWARE - LOCATING SPIGOT - M6 X Ø8 - STAINLESS" placed x (1, 0, 0) y (0, 1, 0) z (0, 0, 1) at (0, 0, 0)
equation "pod_w_Ref = 2500 mm" comment "DECIDED: D-01; conventions s4 (X = +-1250)"
equation "pod_d_Ref = 1700 mm" comment "DECIDED: D-01; conventions s4 (Y = +-850)"
equation "pod_h_Ref = 2400 mm" comment "DECIDED: D-21 (room floor to roof skin top)"
equation "glide_h_Ref = 10 mm" comment "ASSUMPTION: layout study inputs.py glide_h"
equation "band_h_Ref = 100 mm" comment "SOURCE: layout study B1 list B-BAND 100x40; inputs.py base_h"
equation "outer_t_Ref = 46 mm" comment "DECIDED: PM ruling 2026-10-31: ACP 3 + bond line 3 + frame 40, walls and ceiling (was 43)"
equation "cav_gap_Ref = 4 mm" comment "DECIDED: D-16, D-42: the gap between the outer panel and the lining cassette in the wall and ceiling stack"